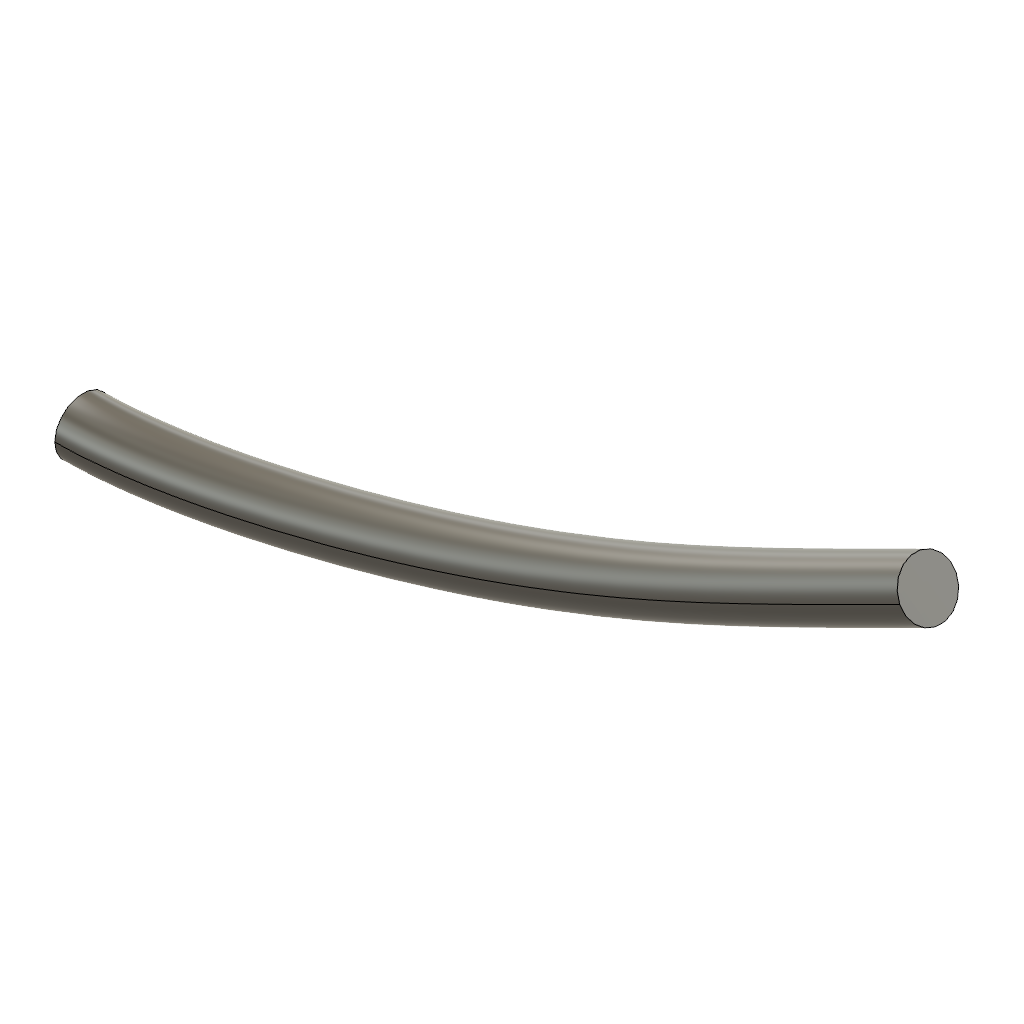
rational_cubic (Autodesk Fusion 360 design; units mm, degrees)
part number: 2026-10-21-16-32-33-426
Autodesk Fusion 360 part; units mm, degrees
sketch "OwnedNurbsSweepPath_rational_cubic" plane through (0, 0, 0) normal (0, 0, 1) x (1, 0, 0)
  spline S0 degree 3 poles (0, 0) (20, 0) (40, 10) (60, 20) knots 0 0 0 0 1 1 1 1 weights 1 0.7 1.3 1
sketch "OwnedNurbsSweepCircle_rational_cubic" plane through (0, 0, 0) normal (1, 0, 0) x (0, 0, -1)
  circle A0 centre (0, 0) radius 2
sweep "OwnedFixedNurbsSweep_rational_cubic" add profiles "OwnedNurbsSweepCircle_rational_cubic" path "OwnedNurbsSweepPath_rational_cubic" along S0 section 1
